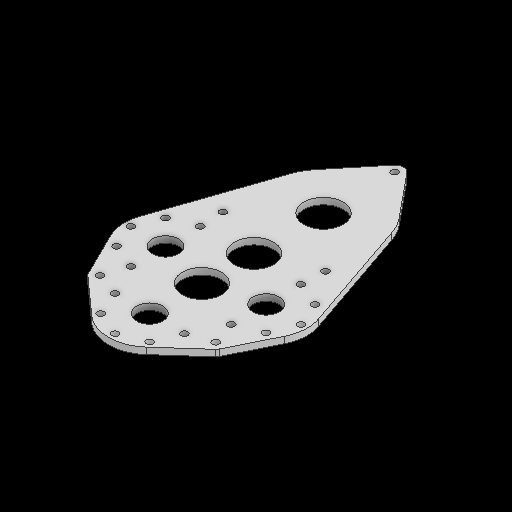
# Autodesk Inventor part: onshape
Saved by Autodesk Inventor 2027.1 (Build 311270010, 270A)
## iProperties
Created: 2026-10-31
Part Number: onshape
Material: Generic
Document SubType Name: Modeling
Designer: Stanley Ruangsuwan
Density: 1 g/cm^3
Appearance: Default
Author: Stanley Ruangsuwan
Autodesk Inventor part; units mm, degrees
ref_plane "YZ Plane" through (0, 0, 0) normal (1, 0, 0) x (0, 1, 0)
ref_plane "XZ Plane" through (0, 0, 0) normal (0, 1, 0) x (-1, 0, 0)
ref_plane "XY Plane" through (0, 0, 0) normal (0, 0, 1) x (1, 0, 0)
sketch "Sketch1" plane through (0, 0, 0) normal (0, 1, 0) x (-1, 0, 0)
  circle A0 centre (36.7799, -18.3459) radius 25.4 construction
  circle A1 centre (0, 30.0609) radius 25.4 construction
  circle A2 centre (-36.7799, -18.3459) radius 25.4 construction
  circle A3 centre (36.7799, -18.3459) radius 30.0609
  circle A4 centre (-36.7799, -18.3459) radius 30.0609
  circle A5 centre (0, 30.0609) radius 30.0609
  circle A6 centre (36.7799, -18.3459) radius 13.97 construction
  circle A7 centre (-36.7799, -18.3459) radius 13.97 construction
  circle A8 centre (0, 30.0609) radius 13.97 construction
  circle A9 centre (0, -8.1153) radius 26.67 construction
  circle A10 centre (0, -8.1153) radius 14.2875
  circle A11 centre (0, -46.2915) radius 13.97 construction
  circle A12 centre (0, -97.1677) radius 39.37
  circle A13 centre (36.7799, -43.7459) radius 2.4892
  circle A14 centre (54.7404, -36.3064) radius 2.4892
  circle A15 centre (62.1799, -18.3459) radius 2.4892
  circle A16 centre (54.7404, -0.3853) radius 2.4892
  circle A17 centre (36.7799, 7.0541) radius 2.4892
  line L0 (0, -8.1153) -> (0, -46.2915) construction
  circle A18 centre (-36.7799, -43.7459) radius 2.4892
  circle A19 centre (-54.7404, -36.3064) radius 2.4892
  circle A20 centre (-62.1799, -18.3459) radius 2.4892
  circle A21 centre (-54.7404, -0.3853) radius 2.4892
  circle A22 centre (-36.7799, 7.0541) radius 2.4892
  circle A23 centre (0, -46.2915) radius 14.2875
  circle A24 centre (0, -97.1677) radius 14.2875
  circle A25 centre (0, 30.0609) radius 9.525
  circle A26 centre (36.7799, -18.3459) radius 9.525
  circle A27 centre (-36.7799, -18.3459) radius 9.525
  circle A28 centre (25.4, 30.0609) radius 2.4892
  circle A29 centre (17.9605, 48.0214) radius 2.4892
  circle A30 centre (0, 55.4609) radius 2.4892
  circle A31 centre (-17.9605, 48.0214) radius 2.4892
  circle A32 centre (-25.4, 30.0609) radius 2.4892
  circle A33 centre (37.5551, -61.0997) radius 2.4892
  circle A34 centre (37.5551, -61.0997) radius 6.35 construction
  line L1 (32.9752, -65.4983) -> (28.3953, -69.8968) construction
  line L2 (37.44, -54.7508) -> (37.3249, -48.4018) construction
  circle A35 centre (-37.5551, -61.0997) radius 2.4892
  circle A36 centre (-37.5551, -61.0997) radius 6.35 construction
  line L3 (-32.9752, -65.4983) -> (-28.3953, -69.8968) construction
  line L4 (-37.44, -54.7508) -> (-37.3249, -48.4018) construction
  circle A37 centre (42.3367, 24.0525) radius 2.4892
  circle A38 centre (42.3367, 24.0525) radius 6.35
  line L5 (41.5115, 17.7563) -> (40.6863, 11.4601) construction
  line L6 (36.0497, 24.9447) -> (29.7627, 25.837) construction
  circle A39 centre (-42.3367, 24.0525) radius 2.4892
  circle A40 centre (-42.3367, 24.0525) radius 6.35
  line L7 (20.0185, 52.4867) -> (46.5653, 28.7896)
  line L8 (48.0338, 26.857) -> (63.75, -5.0693)
  line L9 (-20.0185, 52.4867) -> (-46.5653, 28.7896)
  line L10 (-48.0338, 26.857) -> (-63.75, -5.0693)
  circle A41 centre (0, -149.2377) radius 2.4892
  circle A42 centre (0, -149.2377) radius 6.35
  line L11 (0, -142.8877) -> (0, -136.5377) construction
  line L12 (-65.225, -28.0686) -> (-37.2539, -109.9014)
  line L13 (65.225, -28.0686) -> (37.2539, -109.9014)
  line L14 (30.4414, -122.134) -> (4.9099, -153.2645)
  line L15 (-30.4414, -122.134) -> (-4.9099, -153.2645)
  point P0 (0, 0)
  point P1 (36.2511, 22.2392)
  point P2 (36.3744, 26.2373)
  dimension "d1" = 50.8
  dimension "d5" = 60.1218
  dimension "d8" = 27.94
  dimension "d9" = 53.34
  dimension "d10" = 38.1762
  dimension "d11" = 38.1762
  dimension "d13" = 38.1762
  dimension "d14" = 28.575
  dimension "d15" = 60.7945
  dimension "d16" = 38.1762
  dimension "d17" = 78.74
  dimension "d18" = 50.8762
  dimension "d19" = 4.9784
  dimension "d22" = 180
  dimension "d29" = 28.575
  dimension "d31" = 19.05
  dimension "d33" = 4.9784
  dimension "d36" = 180
  dimension "d38" = 4.9784
  dimension "d41" = 12.7
  dimension "d42" = 6.35
  dimension "d43" = 4.9784
  dimension "d44" = 12.7
  dimension "d47" = 4.9784
  dimension "d48" = 12.7
  constraints: 41 centre point, 32 end point, 31 point on circle, 17 coincident, 16 tangent, 13 symmetric about line, 10 point on line, 8 equal radius, 8 vertical alignment, 4 equal length, 3 horizontal alignment, 2 vertical, 32 other
  measures "d5" diameter of A5
  measures "d8" diameter of A8
  measures "d9" diameter of A9
  measures "d10" distance of A9.centre A6.centre
  measures "d11" distance of A7.centre A9.centre
  measures "d13" distance of A8.centre A9.centre
  measures "d14" diameter of A10
  measures "d15" distance of A5.centre A7.centre
  measures "d16" distance of A9.centre L0.end
  measures "d17" diameter of A12
  measures "d18" distance of L0.end A12.centre
  measures "d19" diameter of A13
  measures "d29" diameter of A24
  measures "d31" diameter of A26
  measures "d33" diameter of A28
  measures "d38" diameter of A33
  measures "d41" diameter of A34
  measures "d42" distance of L1.start L1.end
  measures "d43" diameter of A37
  measures "d44" diameter of A38
  measures "d47" diameter of A41
  measures "d48" diameter of A42
extrude "Extrusion1" add sketch "Sketch1" along normal blind 4.7625 contours A3 A10 | A3 A10 A5 L7 A38 L8 | L13 A12 A23 L12 A4 A10 A3 | A38 | A12 A23 | A10 A5 | A4 A10 | L14 A42 L15 A12 | A10 A4 L10 A40 L9 A5 | A42 | A40 picked at (29.5618, -37.6747) picked at (-8.372, -68.1952) picked at (-19.4323, 22.8031) picked at (-29.5618, -37.6747)
equation "\"d10\" = d11"
equation "\"d13\" = d11"
equation "\"d16\" = d11"
body "Solid1"
